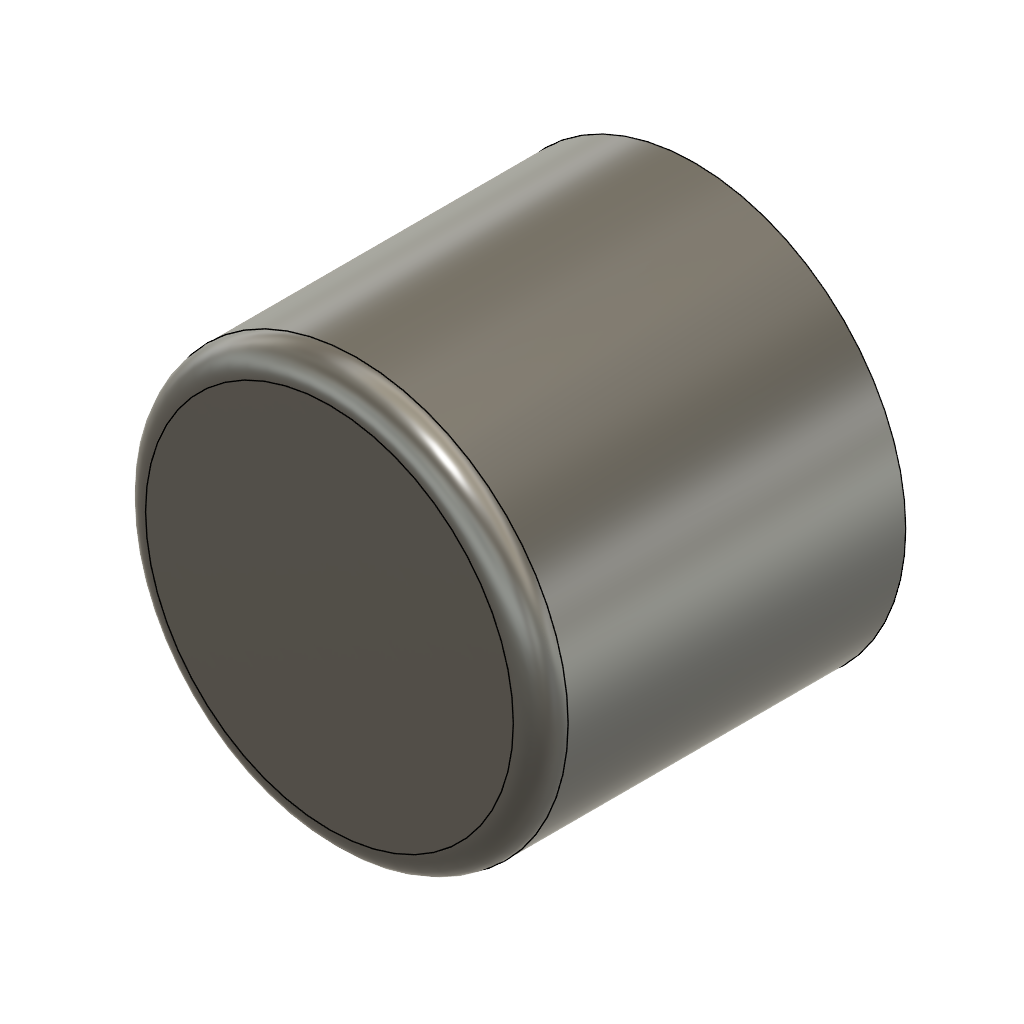
Native (Autodesk Fusion 360 design; units mm, degrees)
part number: 2026-11-25-22-58-35-103
Autodesk Fusion 360 part; units mm, degrees
sketch "Disc sketch" plane through (0, 0, 0) normal (0, 0, 1) x (1, 0, 0)
  circle A0 centre (0, 0) radius 23.9
extrude "Disc extrude" add sketch "Disc sketch" along normal blind 41.3
fillet "Rim round" radius 3.1 1 edges at (-22.2826, -8.6426, 41.3)
